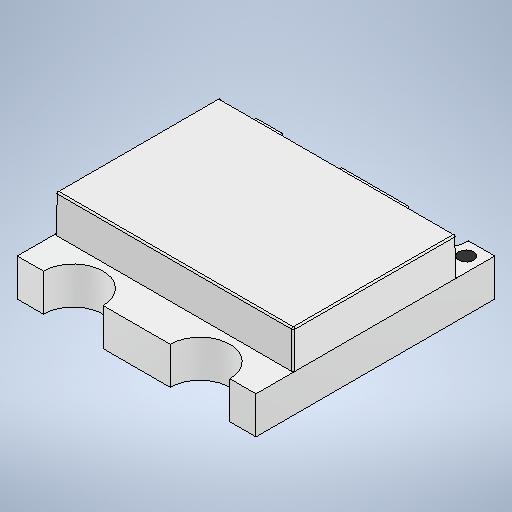
# Autodesk Inventor part: APTF1616LSEEZGKQBKC
Saved by Autodesk Inventor 2025.2 (Build 292293000, 293)
## iProperties
Created: 2025-09-13
Part Number: APTF1616LSEEZGKQBKC
Material: Generic
Document SubType Name: Modeling
Designer: K. Paulsen
Density: 1 g/cm^3
Appearance: Default
Author: K. Paulsen
Autodesk Inventor part; units mm, degrees
ref_plane "YZ Plane" through (0, 0, 0) normal (1, 0, 0) x (0, 1, 0)
ref_plane "XZ Plane" through (0, 0, 0) normal (0, 1, 0) x (-1, 0, 0)
ref_plane "XY Plane" through (0, 0, 0) normal (0, 0, 1) x (1, 0, 0)
sketch "Sketch1" plane through (0, 0, 0) normal (0, 1, 0) x (-1, 0, 0)
  line L0 (-0.8, -0.8) -> (0.8, -0.8)
  line L1 (0.8, -0.8) -> (0.8, 0.8)
  line L2 (0.8, 0.8) -> (-0.8, 0.8)
  line L3 (-0.8, 0.8) -> (-0.8, -0.8)
  line L4 (-0.8, -0.8) -> (0.8, 0.8) construction
  line L5 (0.8, -0.8) -> (-0.8, 0.8) construction
  circle A0 centre (0.425, 0.8) radius 0.2
  circle A1 centre (-0.425, 0.8) radius 0.2
  line L6 (0, 0.8) -> (0, -0.8) construction
  line L7 (0.8, 0) -> (-0.8, 0) construction
  circle A2 centre (0.425, -0.8) radius 0.2
  circle A3 centre (-0.425, -0.8) radius 0.2
  point P0 (0, 0)
  point P1 (0.625, 0.8)
  point P2 (0.225, 0.8)
  point P3 (-0.225, 0.8)
  point P4 (-0.625, 0.8)
  point P5 (-0.625, -0.8)
  point P6 (-0.225, -0.8)
  point P7 (0.225, -0.8)
  point P8 (0.625, -0.8)
  dimension "d0" = 1.6
  dimension "d1" = 1.6
  dimension "d2" = 0.4
  dimension "d3" = 0.85
  constraints: 16 end point, 6 midpoint, 4 centre point, 2 parallel, 2 point on line, 2 symmetric about line, 1 equal radius, 1 horizontal, 1 perpendicular, 3 other
  measures "d0" distance of L2.end L1.end
  measures "d1" distance of L1.end L0.end
  measures "d2" diameter of A0
  measures "d3" distance of A1.centre A0.centre
extrude "Extrusion1" add sketch "Sketch1" along normal blind 0.25 contours A2 L0 A3 L3 L2 A1 A0 L1
sketch "Sketch2" plane through (0, 0.25, 0) normal (0, 1, 0) x (1, 0, 0)
  line L0 (-0.8, 0.8) -> (-0.8, -0.8) projected
  line L1 (0.8, 0.55) -> (-0.8, 0.55)
  line L2 (-0.8, 0.55) -> (-0.8, -0.55)
  line L3 (-0.8, -0.55) -> (0.8, -0.55)
  line L4 (0.8, -0.55) -> (0.8, 0.55)
  line L5 (0.8, 0.55) -> (-0.8, -0.55) construction
  line L6 (-0.8, 0.55) -> (0.8, -0.55) construction
  point P0 (0, 0)
  dimension "d6" = 1.6
  dimension "d7" = 1.1
  constraints: 12 end point, 2 midpoint, 2 parallel, 1 horizontal, 1 perpendicular, 1 point on line
  measures "d6" distance of L3.end L2.end
  measures "d7" distance of L2.end L1.end
extrude "Extrusion2" add sketch "Sketch2" along normal blind 0.25 draft -1
fillet "Fillet1" radius 0.01 8 edges at (0, 0.5, 0.5456) (0, 0.5, -0.5456) (0.7956, 0.5, 0) (-0.7956, 0.5, 0) (-0.7978, 0.375, 0.5478) (0.7978, 0.375, 0.5478) (0.7978, 0.375, -0.5478) (-0.7978, 0.375, -0.5478)
sketch "Sketch3" plane through (0, 0.25, 0) normal (0, 1, 0) x (1, 0, 0)
  circle A0 centre (0.7046, 0.7046) radius 0.05
  circle A1 centre (0.7046, 0.7046) radius 0.0954 construction
  arc A2 (0.225, 0.8) -> (0.625, 0.8) centre (0.425, 0.8) ccw projected
  line L0 (0.8, 0.8) -> (0.625, 0.8) projected
  line L1 (0.8, 0.54) -> (0.8, 0.8) projected
  point P0 (0, 0)
  dimension "d11" = 0.1
  constraints: 3 tangent, 2 centre point
  measures "d11" diameter of A0
split_face "Split1"
sketch "Sketch4" plane through (0, 0, 0) normal (0, -1, 0) x (1, 0, 0)
  line L0 (0.8, 0.8) -> (0.8, -0.8) projected
  line L1 (-0.8, -0.8) -> (-0.8, 0.8) projected
  line L2 (0.8, 0) -> (-0.8, 0)
  line L3 (-0.8, 0) -> (-0.8, -0.3)
  line L4 (-0.8, -0.3) -> (0.8, -0.3)
  line L5 (0.8, -0.3) -> (0.8, 0)
  line L6 (0.35, 0) -> (-0.35, 0)
  line L7 (-0.35, 0) -> (-0.35, 0.3)
  line L8 (-0.35, 0.3) -> (0.35, 0.3)
  line L9 (0.35, 0.3) -> (0.35, 0)
  line L10 (0, 0) -> (0, -0.8) construction
  dimension "d12" = 0.3
  dimension "d13" = 0.3
  dimension "d14" = 0.7
  constraints: 18 end point, 4 parallel, 2 horizontal, 2 perpendicular, 2 point on line, 1 midpoint, 1 vertical, 1 other
  measures "d12" distance between parallel lines of L4 L2
  measures "d13" distance between parallel lines of L2 L8
  measures "d14" distance of L7.end L8.end
split_face "Split2"
split_face "Split3"
sketch "Sketch5" plane through (0.425, 0, 0.8) normal (0, -1, 0) x (1, 0, 0)
  arc A0 (-0.2, 0) -> (0.2, 0) centre (0, 0) ccw construction
  arc A1 (0.2, -1.6) -> (-0.2, -1.6) centre (0, -1.6) ccw construction
  line L0 (0, 0) -> (0, -1.6) construction
  arc A2 (-1.05, 0) -> (-0.65, 0) centre (-0.85, 0) ccw construction
  arc A3 (-0.65, -1.6) -> (-1.05, -1.6) centre (-0.85, -1.6) ccw construction
  line L1 (-0.85, 0) -> (-0.85, -1.6) construction
  line L2 (0.2, 0) -> (0.375, 0) construction
  line L3 (0.325, 0) -> (-0.325, 0)
  line L4 (-0.325, 0) -> (-0.325, -0.35)
  line L5 (-0.325, -0.35) -> (0.325, -0.35)
  line L6 (0.325, -0.35) -> (0.325, 0)
  line L7 (-1.225, -1.1) -> (-1.225, -0.8) projected
  line L8 (0.375, 0) -> (0.375, -0.8) projected
  line L9 (-1.225, -0.8) -> (0.375, -0.8) construction
  line L10 (-0.65, 0) -> (-0.2, 0) projected
  line L11 (-0.425, 0) -> (-0.425, -1.6) construction
  line L12 (-0.2, -1.6) -> (-0.65, -1.6) projected
  line L13 (0.325, -1.6) -> (-0.325, -1.6)
  line L14 (-0.325, -1.6) -> (-0.325, -1.25)
  line L15 (-0.325, -1.25) -> (0.325, -1.25)
  line L16 (0.325, -1.25) -> (0.325, -1.6)
  line L17 (-1.175, 0) -> (-0.525, 0)
  line L18 (-0.525, 0) -> (-0.525, -0.35)
  line L19 (-0.525, -0.35) -> (-1.175, -0.35)
  line L20 (-1.175, -0.35) -> (-1.175, 0)
  line L21 (-0.525, -1.6) -> (-0.525, -1.25)
  line L22 (-0.525, -1.25) -> (-1.175, -1.25)
  line L23 (-1.175, -1.25) -> (-1.175, -1.6)
  line L24 (-1.175, -1.6) -> (-0.525, -1.6)
  point P0 (-0.425, -0.8)
  dimension "d15" = 0.65
  dimension "d16" = 0.35
  constraints: 40 end point, 12 symmetric about line, 2 horizontal, 2 midpoint, 2 parallel, 2 vertical, 1 perpendicular, 1 point on line, 1 other
  measures "d15" distance of L4.end L5.end
  measures "d16" distance of L5.end L3.start
split_face "Split4"
split_face "Split5"
split_face "Split6"
split_face "Split7"
equation "\"d13\" = d12"
body "Solid1"
